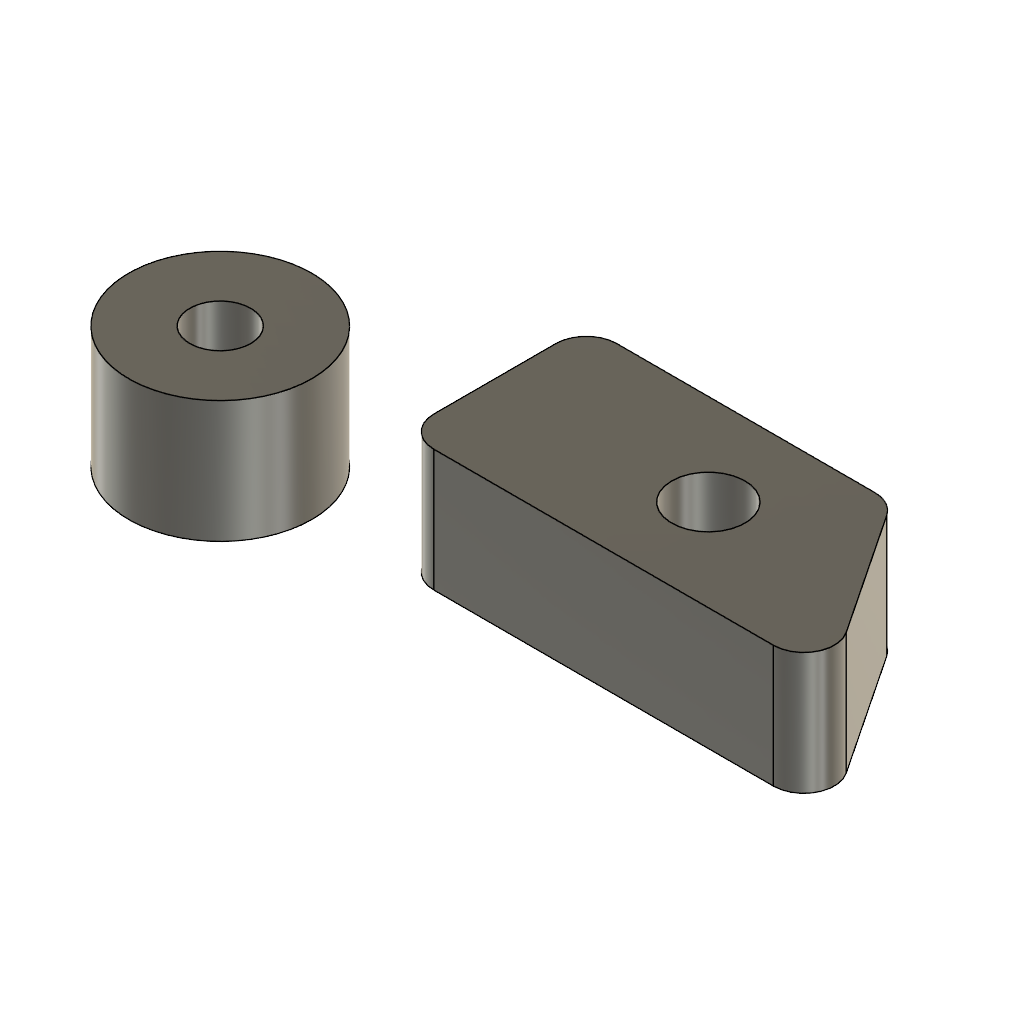
probe-model (Autodesk Fusion 360 design; units mm, degrees)
part number: 2026-10-16-19-34-40-502
Autodesk Fusion 360 part; units mm, degrees
sketch "Sketch2" plane through (0, 0, 0) normal (0, 0, 1) x (1, 0, 0)
  line L0 (0, 0) -> (70, 0)
  line L1 (70, 0) -> (50, 30)
  line L2 (50, 30) -> (0, 30)
  line L3 (0, 30) -> (0, 0)
  dimension "d1" = 70
  dimension "d2" = 30
  dimension "d3" = 50
  constraint coincident L0.start L3.end
  constraint horizontal L0
  measures "d1" horizontal distance of L0.start L0.end
  measures "d2" vertical distance of L0.end L1.end
  measures "d3" horizontal distance of L1.end L2.end
extrude "Extrude1" add sketch "Sketch2" along normal blind 20 makes body 1
fillet "Fillet1" radius 5 4 edges at (0, 30, 10) (50, 30, 10) (70, 0, 10) (0, 0, 10) on bodies 1
sketch "Sketch3" plane through (0, 0, 20) normal (0, 0, 1) x (1, 0, 0)
  line L0 (5, 0) -> (60.6574, 0)
  line L1 (64.8177, 7.7735) -> (51.4843, 27.7735)
  line L2 (47.3241, 30) -> (5, 30)
  line L3 (0, 25) -> (0, 5)
  circle A0 centre (35, 15) radius 6
  arc A1 (0, 5) -> (5, 0) centre (5, 5) ccw
  arc A2 (60.6574, 0) -> (64.8177, 7.7735) centre (60.6574, 5) ccw
  arc A3 (51.4843, 27.7735) -> (47.3241, 30) centre (47.3241, 25) ccw
  arc A4 (5, 30) -> (0, 25) centre (5, 25) ccw
  dimension "d8" = 12
  measures "d8" diameter of A0
extrude "Extrude2" cut sketch "Sketch3" against normal through all contours A0 bodies 1
chamfer "Chamfer1" distance 2 angle 45 1 edges at (29.406, 12.8303, 0) tangent chain off on bodies 1
sketch "Sketch4" plane through (0, 0, 0) normal (0, 1, 0) x (1, 0, 0)
  line L0 (-30, 0) -> (-30, -30) construction
  line L1 (-25, 0) -> (-15, 0)
  line L2 (-15, 0) -> (-15, -20)
  line L3 (-15, -20) -> (-25, -20)
  line L4 (-25, -20) -> (-25, 0)
revolve "Revolve1" add sketch "Sketch4" angle 360 about axis through (-30, 0, 0) along (0, 0, 1) separate body makes body 2
